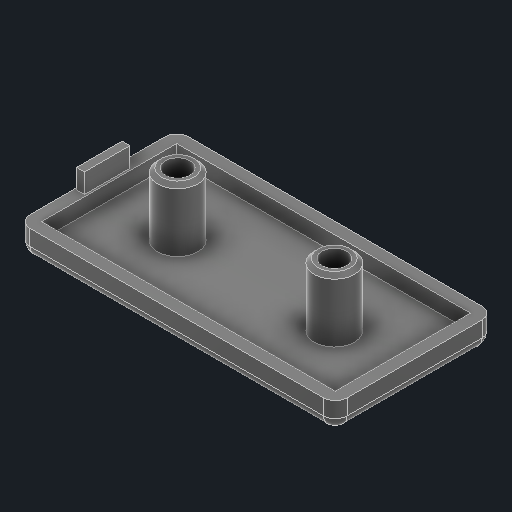
# Autodesk Inventor part: Capa de fechamento frontal retangular
Saved by Autodesk Inventor 2026.1 (Build 301233000, 233)
## iProperties
Created: 2024-10-07
Part Number: Capa de fechamento frontal retangular
Material: Plástico PC/ABS
Document SubType Name: Modeling
Designer: Cliente
Density: 1.15418 g/cm^3
Appearance: Suave - Branco
Mass: 2 g
Surface Area: 26.3513 cm^2
Volume: 1.73284 cm^3
Author: Cliente
Autodesk Inventor part; units mm, degrees
ref_plane "YZ Plane" through (0, 0, 0) normal (1, 0, 0) x (0, 1, 0)
ref_plane "XZ Plane" through (0, 0, 0) normal (0, 1, 0) x (-1, 0, 0)
ref_plane "XY Plane" through (0, 0, 0) normal (0, 0, 1) x (1, 0, 0)
sketch "Esboço1" plane through (0, 0, 0) normal (0, 1, 0) x (-1, 0, 0)
  line L0 (-18.75, 10.125) -> (18.75, 10.125)
  line L1 (20.25, 8.625) -> (20.25, -8.625)
  line L2 (18.75, -10.125) -> (-18.75, -10.125)
  line L3 (-20.25, -8.625) -> (-20.25, 8.625)
  line L4 (-20.25, 10.125) -> (20.25, -10.125) construction
  line L5 (20.25, 10.125) -> (-20.25, -10.125) construction
  circle A0 centre (10, 0) radius 2.575
  circle A1 centre (-10, 0) radius 2.575
  line L6 (10, 0) -> (-10, 0)
  arc A2 (18.75, -10.125) -> (20.25, -8.625) centre (18.75, -8.625) ccw
  arc A3 (20.25, 8.625) -> (18.75, 10.125) centre (18.75, 8.625) ccw
  arc A4 (-18.75, 10.125) -> (-20.25, 8.625) centre (-18.75, 8.625) ccw
  arc A5 (-20.25, -8.625) -> (-18.75, -10.125) centre (-18.75, -8.625) ccw
  line L7 (-18.75, -8.625) -> (18.75, -8.625)
  line L8 (18.75, -8.625) -> (18.75, 8.625)
  line L9 (18.75, 8.625) -> (-18.75, 8.625)
  line L10 (-18.75, 8.625) -> (-18.75, -8.625)
  circle A6 centre (10, 0) radius 1.575
  circle A7 centre (-10, 0) radius 1.575
  point P0 (0, 0)
  dimension "d0" = 40.5
  dimension "d1" = 20.25
  dimension "d2" = 5.15
  dimension "d3" = 5.15
  dimension "d4" = 20
  dimension "d5" = 1.5
  dimension "d6" = 1.5
  dimension "d7" = 1
  dimension "d8" = 1
  constraints: 22 end point, 8 centre point, 8 point on circle, 8 point on line, 8 tangent, 4 parallel, 3 equal radius, 3 midpoint, 2 horizontal, 2 perpendicular, 3 other
  measures "d0" distance of L4.end L5.end
  measures "d1" distance of L5.start L4.end
  measures "d2" diameter of A0
  measures "d3" diameter of A1
  measures "d4" distance of L6.start L6.end
  measures "d5" radius of A2
  measures "d6" distance between parallel lines of L2 L7
  measures "d7" radial gap between concentric circles of A0 A6
  measures "d8" radial gap between concentric circles of A1 A7
extrude "Extrusão1" add sketch "Esboço1" against normal blind 1.5 contours L0 A3 L1 A2 L2 A5 L3 A4 | A0 | A1 | L10 L9 L8 L7 | A6 | A7
extrude "Extrusão2" add sketch "Esboço1" along normal blind 2 contours L0 A3 L1 A2 L2 A5 L3 A4
extrude "Extrusão3" add sketch "Esboço1" along normal blind 8 contours A0 | A1
fillet "Arredondamento1" radius 1.5 8 edges at (19.8107, -1.5, 9.6857) (0, -1.5, 10.125) (-19.8107, -1.5, 9.6857) (-20.25, -1.5, 0) (-19.8107, -1.5, -9.6857) (0, -1.5, -10.125) (19.8107, -1.5, -9.6857) (20.25, -1.5, 0)
chamfer "Chanfro1" distance 0.5 angle 45 2 edges at (12.575, 8, 0) (-7.425, 8, 0)
sketch "Esboço2" plane through (0, 2, 0) normal (0, 1, 0) x (1, 0, 0)
  line L0 (-19, 2.9) -> (-20, 2.9)
  line L1 (-20, 2.9) -> (-20, -2.9)
  line L2 (-20, -2.9) -> (-19, -2.9)
  line L3 (-19, -2.9) -> (-19, 2.9)
  line L4 (-19, 2.9) -> (-20, -2.9) construction
  line L5 (-20, 2.9) -> (-19, -2.9) construction
  line L6 (-20.25, 8.625) -> (-20.25, -8.625) projected
  point P0 (0, 0)
  point P1 (-19.5, 0)
  dimension "d19" = 1
  dimension "d20" = 5.8
  dimension "d21" = 0.25
  constraints: 12 end point, 2 midpoint, 2 parallel, 1 horizontal, 1 horizontal alignment, 1 perpendicular
  measures "d19" distance of L2.end L1.end
  measures "d20" distance of L1.end L0.end
  measures "d21" distance between parallel lines of L1 L6
extrude "Extrusão4" add sketch "Esboço2" along normal blind 2.5
